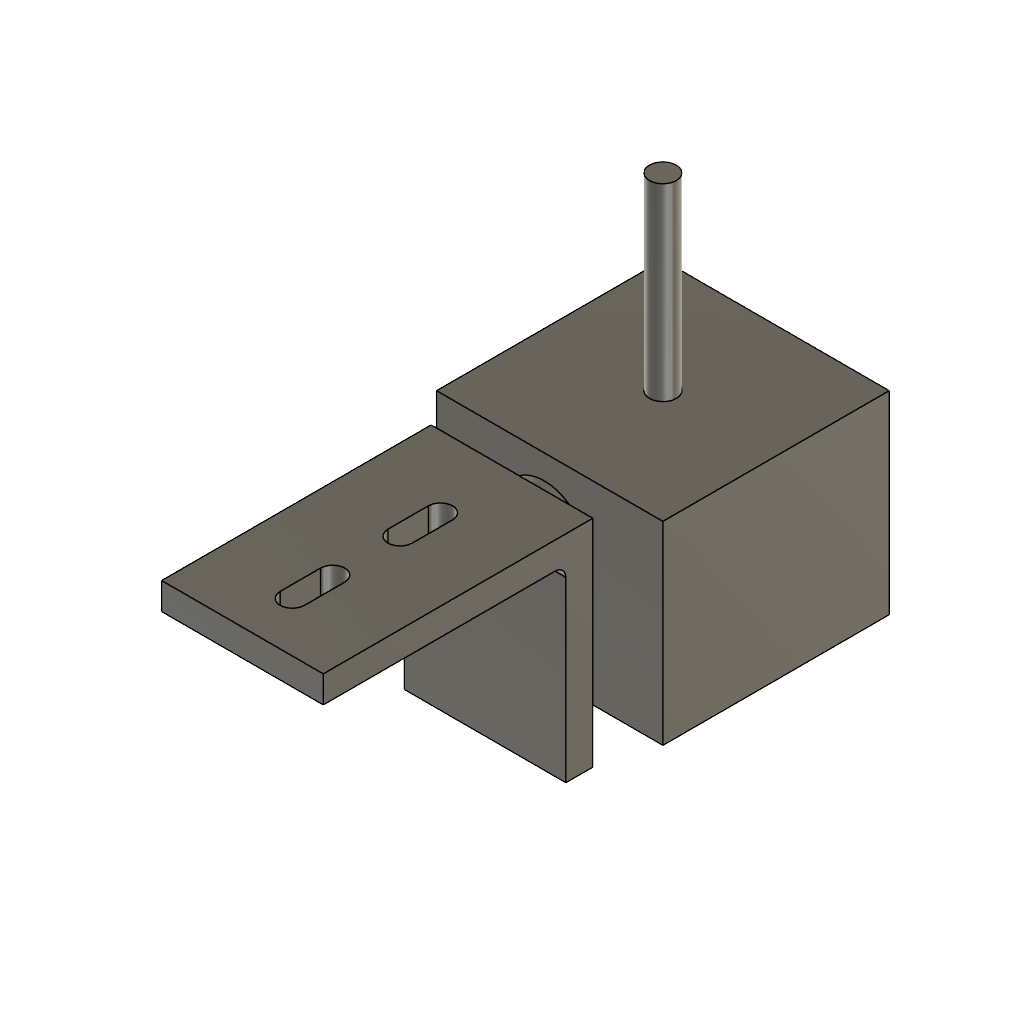
VISION_SWINE_Camera_Mount_V3 (Autodesk Fusion 360 design; units mm, degrees)
part number: 2026-11-25-22-52-52-909
part number: 2026-11-25-22-52-53-193
part number: 2026-11-25-22-52-55-072
part number: 2026-11-25-22-52-57-746
Autodesk Fusion 360 part; units mm, degrees
ref_plane "WorkPlane1" through (30, 0, 0) normal (1, 0, 0) x (0, 1, 0) in component "Camera_L_Bracket_V3"
ref_plane "WorkPlane2" through (0, 0, 50) normal (0, 0, 1) x (1, 0, 0) in component "Camera_L_Bracket_V3"
ref_plane "WorkPlane3" through (0, 5, 0) normal (0, 1, 0) x (0, 0, 1) in component "Camera_L_Bracket_V3"
sketch "Sketch1" plane through (0, 0, 0) normal (0, 0, 1) x (1, 0, 0) in component "Camera_L_Bracket_V3"
  line L0 (0, 0) -> (30, 0)
  line L1 (30, 0) -> (30, 5)
  line L2 (30, 5) -> (0, 5)
  line L3 (0, 5) -> (0, 0)
extrude "Mounting plate leg" add sketch "Sketch1" along normal blind 50 makes body 1 in component "Camera_L_Bracket_V3"
ref_plane "WorkPlane4" through (0, 40, 0) normal (0, 1, 0) x (0, 0, 1) in component "Camera_L_Bracket_V3"
sketch "Sketch2" plane through (0, 0, 50) normal (0, 0, 1) x (1, 0, 0) in component "Camera_L_Bracket_V3"
  line L0 (0, 0) -> (30, 0)
  line L1 (30, 0) -> (30, 40)
  line L2 (30, 40) -> (0, 40)
  line L3 (0, 40) -> (0, 0)
extrude "Camera shelf" add sketch "Sketch2" against normal blind 5 bodies 1 in component "Camera_L_Bracket_V3"
fillet "Inside corner reinforcement" radius 2 1 edges at (15, 5, 45) on bodies 1 in component "Camera_L_Bracket_V3"
ref_plane "WorkPlane5" through (15, 0, 0) normal (1, 0, 0) x (0, 1, 0) in component "Camera_L_Bracket_V3"
ref_plane "WorkPlane6" through (0, 12.5, 0) normal (0, 1, 0) x (0, 0, 1) in component "Camera_L_Bracket_V3"
sketch "Sketch3" plane through (0, 0, 50) normal (0, 0, 1) x (1, 0, 0) in component "Camera_L_Bracket_V3"
  circle A0 centre (15, 12.5) radius 3.5
  dimension "d47" = 7
  measures "d47" diameter of A0
extrude "Camera screw clearance" cut sketch "Sketch3" against normal blind 5 bodies 1 in component "Camera_L_Bracket_V3"
ref_plane "WorkPlane7" through (15, 0, 0) normal (1, 0, 0) x (0, 1, 0) in component "Camera_L_Bracket_V3"
ref_plane "WorkPlane8" through (0, 0, 9.25) normal (0, 0, 1) x (1, 0, 0) in component "Camera_L_Bracket_V3"
ref_plane "WorkPlane9" through (0, 0, 16.75) normal (0, 0, 1) x (1, 0, 0) in component "Camera_L_Bracket_V3"
sketch "Sketch4" plane through (0, 0, 0) normal (0, 1, 0) x (1, 0, 0) in component "Camera_L_Bracket_V3"
  line L0 (12.75, -9.25) -> (12.75, -16.75)
  arc A0 (12.75, -16.75) -> (17.25, -16.75) centre (15, -16.75) ccw
  line L1 (17.25, -16.75) -> (17.25, -9.25)
  arc A1 (17.25, -9.25) -> (12.75, -9.25) centre (15, -9.25) ccw
  line L2 (15, -9.25) -> (15, -16.75) construction
  point P0 (15, -9.25)
  point P1 (15, -16.75)
  dimension "d56" = 4.5
  constraint coincident P0 A1.centre
  constraint coincident P1 A0.centre
  constraint tangent L0 A0
  constraint tangent A0 L1
  constraint tangent L1 A1
  constraint tangent L0 A1
  constraint parallel L0 L1
  measures "d56" diameter of A0
extrude "M4 slot 1" cut sketch "Sketch4" along normal blind 5 bodies 1 in component "Camera_L_Bracket_V3"
ref_plane "WorkPlane10" through (0, 0, 29.25) normal (0, 0, 1) x (1, 0, 0) in component "Camera_L_Bracket_V3"
ref_plane "WorkPlane11" through (0, 0, 36.75) normal (0, 0, 1) x (1, 0, 0) in component "Camera_L_Bracket_V3"
sketch "Sketch5" plane through (0, 0, 0) normal (0, 1, 0) x (1, 0, 0) in component "Camera_L_Bracket_V3"
  line L0 (12.75, -29.25) -> (12.75, -36.75)
  arc A0 (12.75, -36.75) -> (17.25, -36.75) centre (15, -36.75) ccw
  line L1 (17.25, -36.75) -> (17.25, -29.25)
  arc A1 (17.25, -29.25) -> (12.75, -29.25) centre (15, -29.25) ccw
  line L2 (15, -29.25) -> (15, -36.75) construction
  point P0 (15, -29.25)
  point P1 (15, -36.75)
  dimension "d63" = 4.5
  constraint coincident P0 A1.centre
  constraint coincident P1 A0.centre
  constraint tangent L0 A0
  constraint tangent A0 L1
  constraint tangent L1 A1
  constraint tangent L0 A1
  constraint parallel L0 L1
  measures "d63" diameter of A0
extrude "M4 slot 2" cut sketch "Sketch5" along normal blind 5 bodies 1 in component "Camera_L_Bracket_V3"
ref_plane "WorkPlane1" through (20, 0, 0) normal (1, 0, 0) x (0, 1, 0) in component "ELP-USB4K02AF-KL100W_reference"
ref_plane "WorkPlane2" through (0, 12.5, 0) normal (0, 1, 0) x (0, 0, 1) in component "ELP-USB4K02AF-KL100W_reference"
sketch "Sketch1 (2)" plane through (0, 0, 0) normal (0, 0, 1) x (1, 0, 0) in component "ELP-USB4K02AF-KL100W_reference"
  circle A0 centre (20, 12.5) radius 8
  dimension "d70" = 16
  measures "d70" diameter of A0
extrude "Reference mounting boss" add sketch "Sketch1 (2)" against normal blind 6 separate body makes body 2 in component "ELP-USB4K02AF-KL100W_reference"
sketch "Sketch2 (2)" plane through (0, 0, 0) normal (0, 0, 1) x (1, 0, 0) in component "ELP-USB4K02AF-KL100W_reference"
  circle A0 centre (20, 12.5) radius 3
  dimension "d73" = 6
  measures "d73" diameter of A0
extrude "Nominal unthreaded bore" cut sketch "Sketch2 (2)" against normal blind 6 bodies 2 in component "ELP-USB4K02AF-KL100W_reference"
ref_plane "WorkPlane3" through (42, 0, 0) normal (1, 0, 0) x (0, 1, 0) in component "ELP-USB4K02AF-KL100W_reference"
ref_plane "WorkPlane4" through (0, 36, 0) normal (0, 1, 0) x (0, 0, 1) in component "ELP-USB4K02AF-KL100W_reference"
sketch "Sketch3 (2)" plane through (0, 0, 0) normal (0, 0, 1) x (1, 0, 0) in component "ELP-USB4K02AF-KL100W_reference"
  line L0 (0, 0) -> (42, 0)
  line L1 (42, 0) -> (42, 36)
  line L2 (42, 36) -> (0, 36)
  line L3 (0, 36) -> (0, 0)
extrude "Camera housing envelope" add sketch "Sketch3 (2)" along normal blind 42 separate body makes body 3 in component "ELP-USB4K02AF-KL100W_reference"
ref_plane "WorkPlane5" through (21, 0, 0) normal (1, 0, 0) x (0, 1, 0) in component "ELP-USB4K02AF-KL100W_reference"
ref_plane "WorkPlane6" through (0, 0, 21) normal (0, 0, 1) x (1, 0, 0) in component "ELP-USB4K02AF-KL100W_reference"
ref_plane "WorkPlane7" through (0, 36, 0) normal (0, 1, 0) x (0, 0, 1) in component "ELP-USB4K02AF-KL100W_reference"
sketch "Sketch4 (2)" plane through (0, 36, 0) normal (0, 1, 0) x (1, 0, 0) in component "ELP-USB4K02AF-KL100W_reference"
  circle A0 centre (21, -21) radius 9
  dimension "d88" = 18
  measures "d88" diameter of A0
extrude "Lens envelope" add sketch "Sketch4 (2)" along normal blind 10 separate body makes body 4 in component "ELP-USB4K02AF-KL100W_reference"
sketch "Sketch5 (2)" plane through (0, 0, 0) normal (0, 1, 0) x (1, 0, 0) in component "ELP-USB4K02AF-KL100W_reference"
  circle A0 centre (21, -21) radius 2.5
  dimension "d91" = 5
  measures "d91" diameter of A0
extrude "USB cable envelope" add sketch "Sketch5 (2)" against normal blind 35 separate body makes body 5 in component "ELP-USB4K02AF-KL100W_reference"
ref_plane "WorkPlane1" through (0, 0, 45) normal (0, 0, 1) x (1, 0, 0) in component "Camera_screw_head_reference"
ref_plane "WorkPlane2" through (15, 0, 0) normal (1, 0, 0) x (0, 1, 0) in component "Camera_screw_head_reference"
ref_plane "WorkPlane3" through (0, 12.5, 0) normal (0, 1, 0) x (0, 0, 1) in component "Camera_screw_head_reference"
sketch "Sketch1 (3)" plane through (0, 0, 45) normal (0, 0, 1) x (1, 0, 0) in component "Camera_screw_head_reference"
  circle A0 centre (15, 12.5) radius 5
  dimension "d100" = 10
  measures "d100" diameter of A0
extrude "Flat cylindrical head" add sketch "Sketch1 (3)" against normal blind 4 separate body makes body 6 in component "Camera_screw_head_reference"
component "Camera_L_Bracket_V3" placed x (1, 0, 0) y (0, 0, -1) z (0, 1, 0) at (0, 0, 0)
component "ELP-USB4K02AF-KL100W_reference" placed x (1, 0, 0) y (0, 0, -1) z (0, 1, 0) at (-5, 56, 0)
component "Camera_screw_head_reference" placed x (1, 0, 0) y (0, 0, -1) z (0, 1, 0) at (0, 0, 0)
equation "camWidth = 30 mm" comment "VISION SWINE | camera bracket V3"
equation "camReach = 40 mm" comment "VISION SWINE | camera bracket V3"
equation "camHeight = 50 mm" comment "VISION SWINE | camera bracket V3"
equation "camT = 5 mm" comment "VISION SWINE | camera bracket V3"
equation "camRootR = 2 mm" comment "VISION SWINE | camera bracket V3"
equation "camBodyWidth = 42 mm" comment "VISION SWINE | camera bracket V3"
equation "camBodyHeight = 42 mm" comment "VISION SWINE | camera bracket V3"
equation "camBodyDepth = 36 mm" comment "VISION SWINE | camera bracket V3"
equation "camE = 12.5 mm" comment "VISION SWINE | camera bracket V3"
equation "camF = 20 mm" comment "VISION SWINE | camera bracket V3"
equation "camRefD = 6 mm" comment "VISION SWINE | camera bracket V3"
equation "camPadH = 6 mm" comment "VISION SWINE | camera bracket V3"
equation "camPadOD = 16 mm" comment "VISION SWINE | camera bracket V3"
equation "camLensOD = 18 mm" comment "VISION SWINE | camera bracket V3"
equation "camLensL = 10 mm" comment "VISION SWINE | camera bracket V3"
equation "camCableOD = 5 mm" comment "VISION SWINE | camera bracket V3"
equation "camCableL = 35 mm" comment "VISION SWINE | camera bracket V3"
equation "camHeadOD = 10 mm" comment "VISION SWINE | camera bracket V3"
equation "camHeadH = 4 mm" comment "VISION SWINE | camera bracket V3"
equation "camDriverOD = 10 mm" comment "VISION SWINE | camera bracket V3"
equation "camHoleD = 7 mm" comment "VISION SWINE | camera bracket V3"
equation "camHoleX = camWidth / 2" comment "VISION SWINE | camera bracket V3"
equation "camHoleY = 12.5 mm" comment "VISION SWINE | camera bracket V3"
equation "camSlotL = 12 mm" comment "VISION SWINE | camera bracket V3"
equation "camSlotW = 4.5 mm" comment "VISION SWINE | camera bracket V3"
equation "camSlotPitch = 20 mm" comment "VISION SWINE | camera bracket V3"
equation "camSlotLowerZ = 13 mm" comment "VISION SWINE | camera bracket V3"
equation "camSlotX = camWidth / 2" comment "VISION SWINE | camera bracket V3"
equation "d29 = camWidth"
equation "d31 = camHeight"
equation "d33 = camT"
equation "d35 = camHeight"
equation "d37 = camReach"
equation "d39 = -( camT )"
equation "d42 = camRootR"
equation "d43 = camHoleX"
equation "d45 = camHoleY"
equation "d47 = camHoleD"
equation "d48 = -( camT )"
equation "d50 = camSlotX"
equation "d52 = ( camSlotLowerZ ) - ( camSlotL - camSlotW ) / 2"
equation "d54 = ( camSlotLowerZ ) + ( camSlotL - camSlotW ) / 2"
equation "d57 = camT"
equation "d59 = ( camSlotLowerZ + camSlotPitch ) - ( camSlotL - camSlotW ) / 2"
equation "d61 = ( camSlotLowerZ + camSlotPitch ) + ( camSlotL - camSlotW ) / 2"
equation "d64 = camT"
equation "d66 = camF"
equation "d68 = camE"
equation "d70 = camPadOD"
equation "d71 = -( camPadH )"
equation "d73 = camRefD"
equation "d74 = -( camPadH )"
equation "d76 = camBodyWidth"
equation "d78 = camBodyDepth"
equation "d80 = camBodyHeight"
equation "d82 = camBodyWidth / 2"
equation "d84 = camBodyHeight / 2"
equation "d86 = camBodyDepth"
equation "d88 = camLensOD"
equation "d89 = camLensL"
equation "d91 = camCableOD"
equation "d92 = -( camCableL )"
equation "d94 = camHeight - camT"
equation "d96 = camHoleX"
equation "d98 = camHoleY"
equation "d100 = camHeadOD"
equation "d101 = -( camHeadH )"
named bodies: "ELP_Camera_L_Bracket_V3", "Mounting boss", "Housing", "Lens", "USB cable", "Simulated screw head"
